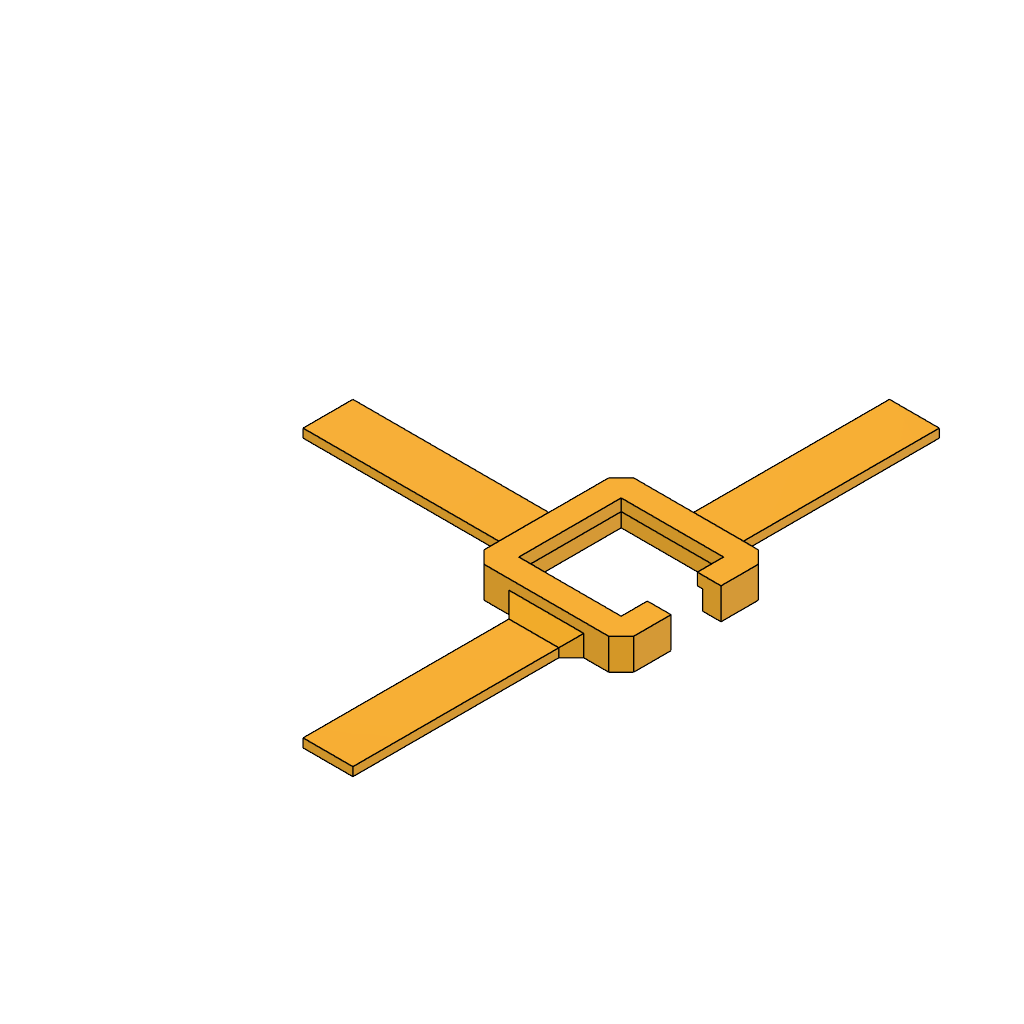
eFleshSensorPackageHolder (Autodesk Fusion 360 design; units mm, degrees)
Autodesk Fusion 360 part; units mm, degrees
box "BoxPrimitive1" add length 235 width 235 height 7 placed x (0, 0, 1) y (1, 0, 0) z (0, 1, 0) at (-42.9228, 0, -19.1157) makes body 1
sketch "Sketch3" plane through (0, 7, 0) normal (0, 1, 0) x (-1, 0, 0)
  line L0 (42.9228, 215.8843) -> (-192.0772, 215.8843)
  line L1 (-192.0772, 215.8843) -> (-192.0772, -19.1157)
  line L2 (-192.0772, -19.1157) -> (42.9228, -19.1157)
  line L3 (42.9228, -19.1157) -> (42.9228, 215.8843)
  line L4 (-52.0772, 75.8843) -> (-97.0772, 75.8843)
  line L5 (-97.0772, 75.8843) -> (-97.0772, 120.8843)
  line L6 (-97.0772, 120.8843) -> (-52.0772, 120.8843)
  line L7 (-52.0772, 120.8843) -> (-52.0772, 75.8843)
  line L8 (-54.5772, 78.3843) -> (-94.5772, 78.3843)
  line L9 (-94.5772, 78.3843) -> (-94.5772, 118.3843)
  line L10 (-94.5772, 118.3843) -> (-54.5772, 118.3843)
  line L11 (-54.5772, 118.3843) -> (-54.5772, 78.3843)
  line L12 (-74.5772, 78.3843) -> (-74.5772, 75.8843) construction
  line L13 (-74.5772, 120.8843) -> (-74.5772, 118.3843) construction
  line L14 (-74.5772, 75.8843) -> (-74.5772, -19.1157) construction
  line L15 (-74.5772, 120.8843) -> (-74.5772, 215.8843) construction
  dimension "d8" = 45
  dimension "d9" = 45
  dimension "d10" = 40
  dimension "d11" = 40
  constraint horizontal L4
  constraint vertical L5
  constraint horizontal L6
  constraint vertical L7
  constraint horizontal L8
  constraint vertical L9
  constraint horizontal L10
  constraint vertical L11
  constraint midpoint L8 L12.start
  constraint midpoint L4 L12.end
  constraint vertical L12
  constraint midpoint L6 L13.start
  constraint midpoint L10 L13.end
  constraint equal L12 L13
  constraint coincident L2 L14.end
  constraint midpoint L2 L14.end
  constraint midpoint L0 L15.end
  constraint vertical L14
  constraint equal L14 L15
  measures "d8" distance of L4.start L4.end
  measures "d9" distance of L4.start L6.end
  measures "d10" distance of L8.start L8.end
  measures "d11" distance of L8.start L10.end
extrude "Extrude1" add sketch "Sketch3" along normal blind 30 separate body contours L8 L9 L10 L11 makes body 2
extrude "Extrude2" add sketch "Sketch3" along normal blind 7.25 contours L4 L5 L6 L7 bodies 2
sketch "Sketch4" plane through (0, 7, 0) normal (0, 1, 0) x (-1, 0, 0)
  line L0 (-84.5772, -19.1157) -> (-84.5772, 215.8843)
  line L1 (-64.5772, 215.8843) -> (-64.5772, -19.1157)
  line L2 (-74.5772, -19.1157) -> (-74.5772, 215.8843) construction
  line L3 (42.9228, -19.1157) -> (42.9228, 215.8843) construction
  line L4 (-192.0772, 215.8843) -> (-192.0772, -19.1157) construction
  line L5 (-44.5772, 128.3843) -> (-104.5772, 128.3843)
  line L6 (-104.5772, 128.3843) -> (-104.5772, 68.3843)
  line L7 (-104.5772, 68.3843) -> (-44.5772, 68.3843)
  line L8 (-44.5772, 68.3843) -> (-44.5772, 128.3843)
  line L9 (-74.5772, 68.3843) -> (-74.5772, 128.3843) construction
  line L10 (-52.0772, 75.8843) -> (-97.0772, 75.8843) construction
  line L11 (42.9228, 215.8843) -> (-192.0772, 215.8843)
  line L12 (-192.0772, -19.1157) -> (42.9228, -19.1157)
  line L13 (-64.5772, -19.1157) -> (-84.5772, -19.1157)
  line L14 (-64.5772, 215.8843) -> (-84.5772, 215.8843)
  line L15 (-44.5772, 98.3843) -> (-104.5772, 98.3843)
  line L16 (-104.5772, 88.3843) -> (-88.6392, 88.3843)
  line L17 (-88.6392, 88.3843) -> (-88.6392, 108.3843)
  line L18 (-88.6392, 108.3843) -> (-104.5772, 108.3843)
  line L19 (-88.6392, 108.3843) -> (42.9228, 108.3843)
  line L20 (-88.6392, 88.3843) -> (42.9228, 88.3843)
  line L21 (42.9228, 88.3843) -> (42.9228, 108.3843)
  point P0 (-74.5772, 98.3843)
  point P1 (-74.5772, 98.3843)
  point P2 (-74.5772, 98.3843)
  point P3 (-74.5772, 98.3843)
  point P4 (-74.5772, -19.1157)
  point P5 (-88.6392, 98.3843)
  dimension "d20" = 7.5
  dimension "d55" = 20
  dimension "d61" = 20
  constraint vertical L0
  constraint vertical L1
  constraint midpoint L2 P3
  constraint coincident P3 P2
  constraint horizontal L5
  constraint vertical L6
  constraint horizontal L7
  constraint vertical L8
  constraint equal L6 L7
  constraint midpoint L7 L9.start
  constraint midpoint L5 L9.end
  constraint midpoint L9 P3
  constraint coincident L1 L13.start
  constraint coincident L0 L13.end
  constraint midpoint L12 P4
  constraint coincident L2 P4
  constraint coincident L2.end L11
  constraint coincident P4 L2.start
  constraint horizontal L13
  constraint midpoint P4 L13
  constraint coincident L0 L14.end
  constraint horizontal L14
  constraint midpoint L2.end L14
  constraint coincident P3 L15
  constraint midpoint L8 L15.start
  constraint midpoint L6 L15.end
  constraint horizontal L16
  constraint vertical L17
  constraint horizontal L18
  constraint coincident L6 L16.start
  constraint coincident L6 L18.end
  constraint midpoint L17 P5
  constraint coincident L15 P5
  constraint coincident L3 L19.end
  constraint perpendicular L3 L19
  constraint coincident L3 L20.end
  constraint perpendicular L3 L20
  measures "d20" distance of L7 L10
  measures "d55" distance of L0 L1
  measures "d61" distance of L16.end L17.end
extrude "Extrude3" add sketch "Sketch4" along normal blind 12.5 separate body contours L0 L6 L7 L16 L20 | L0 L1 L7 L20 | L0 L15 L17 L20 | L0 L1 L15 L20 | L1 L7 L8 L20 | L0 L15 L17 L19 | L0 L1 L15 L19 | L1 L8 L15 L20 | L0 L5 L6 L18 L19 | L0 L1 L5 L19 | L1 L8 L15 L19 | L1 L5 L8 L19 makes body 3
combine "Combine1" operation cut target body 3 tool bodies 2 keep tools
extrude "Extrude4" add sketch "Sketch4" along normal blind 3.5 contours L0 L1 L7 L12 L13 | L8 L19 L20 L21 | L0 L1 L5 L11 L14 bodies 3
move_face "OffsetFaces4" offset -0.5 5 faces at (54.5772, 17.75, 105.051) (81.2438, 17.75, 118.3843) (94.5772, 16, 81.7177) (94.5772, 16, 111.7177) (67.9105, 17.75, 78.3843) on bodies 3
move_face "OffsetFaces5" offset -0.5 1 faces at (81.4105, 14.25, 76.551) on bodies 3
move_face "OffsetFaces6" offset -0.1 5 faces at (97.0772, 9.5833, 80.051) (67.0772, 9.5833, 75.8843) (52.0772, 9.5833, 105.8843) (82.0772, 9.5833, 120.8843) (97.0772, 9.5833, 112.551) on bodies 3
chamfer "Chamfer7" distance 5 angle 45 4 edges at (44.5772, 13.25, 128.3843) (44.5772, 13.25, 68.3843) (104.5772, 13.25, 128.3843) (104.5772, 13.25, 68.3843) tangent chain off on bodies 3
chamfer "Chamfer8" distance 5 angle 45 3 edges at (74.5772, 10.5, 128.3843) (74.5772, 10.5, 68.3843) (44.5772, 10.5, 98.3843) tangent chain off on bodies 3
chamfer "Chamfer9" distance 5 angle 45 6 edges at (64.5772, 11.25, 128.3843) (64.5772, 11.25, 68.3843) (84.5772, 11.25, 68.3843) (84.5772, 11.25, 128.3843) (44.5772, 11.25, 108.3843) (44.5772, 11.25, 88.3843) tangent chain off on bodies 3
hidden bodies 2
named bodies: "Plate", "SensorPackage", "Holder"
